350001_P01_FRONT-DECOR-BLOCK-ASSY-DL_CAD (Autodesk Fusion 360 design; units mm, degrees)
description: FRONT - DECOR BLOCK ASSY - DL | Khối trang trí trái (cụm) | P01
part number: 350001
description: FRONT - DECOR SKIN - DL | Tấm ốp alu khối trái | P01
part number: 351101
description: FRONT - DECOR BACK PLATE - DL | Tấm hậu khối trái | P01
part number: 351102
description: FRONT - DOOR HINGE-SIDE STOP - DL - PIECE 1 | Mặt trước - nẹp chặn cửa phía bản lề - khối trái - đoạn 1 | P01
part number: 351105
description: FRONT - DOOR HINGE-SIDE STOP - DL - PIECE 2 AND 3 | Mặt trước - nẹp chặn cửa phía bản lề - khối trái - đoạn 2 và 3 | P01
part number: 351106
description: FRONT - DOOR HINGE-SIDE STOP - DL - PIECE 4 | Mặt trước - nẹp chặn cửa phía bản lề - khối trái - đoạn 4 | P01
part number: 351107
description: FRONT - FRAME-STOP SEAL - HINGE SIDE 1 | Gioăng chặn cửa phía bản lề | P01
part number: 368005
description: FRONT - FRAME-STOP SEAL - HINGE SIDE 2 AND 3 | Gioăng chặn cửa phía bản lề | P01
description: FRONT - FRAME-STOP SEAL - HINGE SIDE 4 | Gioăng chặn cửa phía bản lề | P01
description: FRONT - DECOR FRAME - DL | Khung trang trí trái (hàn) | P01
part number: 351104
description: FRONT - DECOR FRAME DL - BACK RING BOTTOM | Mặt trước - khung khối trái - vòng sau - thanh dưới | P01
part number: 352101
description: FRONT - DECOR FRAME DL - BACK RING DOOR SIDE | Mặt trước - khung khối trái - vòng sau - thanh phía cửa | P01
part number: 352102
description: FRONT - DECOR FRAME DL - BACK RING SLOPE UNDER DT | Mặt trước - khung khối trái - vòng sau - thanh dốc dưới khối trên | P01
part number: 352103
description: FRONT - DECOR FRAME DL - BACK RING BOLT LINE | Mặt trước - khung khối trái - vòng sau - thanh hàng bu lông | P01
part number: 352104
description: FRONT - DECOR FRAME DL - RING DOOR SIDE - RINGS 1 TO 4 | Mặt trước - khung khối trái - vòng ngang - thanh phía cửa (vòng 1 đến 4) | P01
part number: 352105
description: FRONT - DECOR FRAME DL - RING BACK - RINGS 1 TO 4 | Mặt trước - khung khối trái - vòng ngang - thanh phía sau (vòng 1 đến 4) | P01
part number: 352106
description: FRONT - DECOR FRAME DL - RING BOTTOM - OUTER FACET | Mặt trước - khung khối trái - vòng dưới - thanh mặt vát ngoài | P01
part number: 352107
description: FRONT - DECOR FRAME DL - RING BOTTOM - FRONT FACET | Mặt trước - khung khối trái - vòng dưới - thanh mặt vát trước | P01
part number: 352108
description: FRONT - DECOR FRAME DL - RING OUTER FACET - RINGS 2 TO 4 | Mặt trước - khung khối trái - vòng ngang - thanh mặt vát ngoài (vòng 2 đến 4) | P01
part number: 352109
description: FRONT - DECOR FRAME DL - RING FRONT FACET - RINGS 2 TO 4 | Mặt trước - khung khối trái - vòng ngang - thanh mặt vát trước (vòng 2 đến 4) | P01
part number: 352110
description: FRONT - DECOR FRAME DL - HINGE POST 1 | Mặt trước - khung khối trái - trụ bản lề 1 | P01
part number: 352111
description: FRONT - DECOR FRAME DL - DOOR-SIDE FRONT POST 1 | Mặt trước - khung khối trái - trụ trước phía cửa 1 | P01
part number: 352112
description: FRONT - DECOR FRAME DL - HINGE POST 2 | Mặt trước - khung khối trái - trụ bản lề 2 | P01
part number: 352113
description: FRONT - DECOR FRAME DL - DOOR-SIDE FRONT POST 2 | Mặt trước - khung khối trái - trụ trước phía cửa 2 | P01
part number: 352114
description: FRONT - DECOR FRAME DL - HINGE POST 3 | Mặt trước - khung khối trái - trụ bản lề 3 | P01
part number: 352115
description: FRONT - DECOR FRAME DL - DOOR-SIDE FRONT POST 3 | Mặt trước - khung khối trái - trụ trước phía cửa 3 | P01
part number: 352116
Autodesk Fusion 360 part; units mm, degrees
(part 1 of 3)
sketch "PLAN - DL FACETS (SKELETON)" plane through (0, 0, 0) normal (0, 0, 1) x (1, 0, 0) in component "351101 FRONT - DECOR SKIN - DL"
  line L0 (-1250, -645) -> (-1250, -670)
  line L1 (-1250, -670) -> (-1158, -752)
  line L2 (-1158, -752) -> (-979, -844)
  line L3 (-979, -844) -> (-972, -844)
  line L4 (-972, -844) -> (-972, -645)
  line L5 (-972, -645) -> (-1250, -645)
  point P0 (-5000, -5000)
  dimension "d3208" = 5000
  dimension "d3209" = 5000
  dimension "d3210" = 3750
  dimension "d3211" = 3842
  dimension "d3212" = 4021
  dimension "d3213" = 4028
  dimension "d3214" = 4330
  dimension "d3215" = 4248
  dimension "d3216" = 4156
  dimension "d3217" = 4355
  constraint vertical L0
  constraint vertical L4
  constraint horizontal L3
  constraint horizontal L5
  measures "d3208" horizontal distance of origin P0
  measures "d3209" vertical distance of origin P0
  measures "d3210" horizontal distance of L0.start P0
  measures "d3211" horizontal distance of L1.end P0
  measures "d3212" horizontal distance of L2.end P0
  measures "d3213" horizontal distance of L3.end P0
  measures "d3214" vertical distance of L0.end P0
  measures "d3215" vertical distance of L1.end P0
  measures "d3216" vertical distance of L2.end P0
  measures "d3217" vertical distance of L4.end P0
extrude "EXTRUDE - DL OUTER SHAPE" add sketch "PLAN - DL FACETS (SKELETON)" along normal blind 2290 from surface at 110 makes body 1 in component "351101 FRONT - DECOR SKIN - DL"
sketch "SLOPE - DL TOP UNDER DT" plane through (0, 0, 0) normal (0, 1, 0) x (1, 0, 0) in component "351101 FRONT - DECOR SKIN - DL"
  line L0 (-1250, -2397) -> (-972, -2120)
  line L1 (-972, -2120) -> (-972, -2400)
  line L2 (-972, -2400) -> (-1250, -2400)
  line L3 (-1250, -2400) -> (-1250, -2397)
  point P0 (-5000, 5000)
  dimension "d3221" = 5000
  dimension "d3222" = 5000
  dimension "d3223" = 4028
  dimension "d3224" = 3750
  constraint vertical L1
  constraint vertical L3
  constraint horizontal L2
  measures "d3221" horizontal distance of origin P0
  measures "d3222" vertical distance of origin P0
  measures "d3223" horizontal distance of L0.end P0
  measures "d3224" horizontal distance of L2.end P0
extrude "CUT - DL TOP SLOPE" cut sketch "SLOPE - DL TOP UNDER DT" along normal blind 205 from surface at -850 bodies 1 in component "351101 FRONT - DECOR SKIN - DL"
shell "SHELL - DL SKIN 3 MM (OPEN AT THE BACK AND UNDER DT)" thickness 3 removed faces 3 at (-1036.3333, -747, 110) at (-1036.3333, -747, 2184.1019) at (-1157.3333, -645, 1542.3333) on bodies 1 in component "351101 FRONT - DECOR SKIN - DL"
sketch "POCKET - HINGE H1 (HOLD SPACE)" plane through (0, 0, 0) normal (0, 0, 1) x (1, 0, 0) in component "351101 FRONT - DECOR SKIN - DL"
  line L0 (-1134, -721) -> (-971, -721)
  line L1 (-971, -721) -> (-971, -677)
  line L2 (-971, -677) -> (-1134, -677)
  line L3 (-1134, -677) -> (-1134, -721)
  point P0 (-5000, -5000)
  dimension "d3232" = 5000
  dimension "d3233" = 5000
  dimension "d3234" = 4029
  dimension "d3235" = 3866
  dimension "d3236" = 4279
  dimension "d3237" = 4323
  constraint vertical L1
  constraint vertical L3
  constraint horizontal L0
  constraint horizontal L2
  measures "d3232" horizontal distance of origin P0
  measures "d3233" vertical distance of origin P0
  measures "d3234" horizontal distance of L0.end P0
  measures "d3235" horizontal distance of L2.end P0
  measures "d3236" vertical distance of L0.start P0
  measures "d3237" vertical distance of L1.end P0
extrude "CUT - HINGE POCKET H1 IN THE SKIN" cut sketch "POCKET - HINGE H1 (HOLD SPACE)" along normal blind 124 from surface at 293 bodies 1 in component "351101 FRONT - DECOR SKIN - DL"
sketch "POCKET - HINGE H2 (HOLD SPACE)" plane through (0, 0, 0) normal (0, 0, 1) x (1, 0, 0) in component "351101 FRONT - DECOR SKIN - DL"
  line L0 (-1134, -721) -> (-971, -721)
  line L1 (-971, -721) -> (-971, -677)
  line L2 (-971, -677) -> (-1134, -677)
  line L3 (-1134, -677) -> (-1134, -721)
  point P0 (-5000, -5000)
  dimension "d3241" = 5000
  dimension "d3242" = 5000
  dimension "d3243" = 4029
  dimension "d3244" = 3866
  dimension "d3245" = 4279
  dimension "d3246" = 4323
  constraint vertical L1
  constraint vertical L3
  constraint horizontal L0
  constraint horizontal L2
  measures "d3241" horizontal distance of origin P0
  measures "d3242" vertical distance of origin P0
  measures "d3243" horizontal distance of L0.end P0
  measures "d3244" horizontal distance of L2.end P0
  measures "d3245" vertical distance of L0.start P0
  measures "d3246" vertical distance of L1.end P0
extrude "CUT - HINGE POCKET H2 IN THE SKIN" cut sketch "POCKET - HINGE H2 (HOLD SPACE)" along normal blind 124 from surface at 1047.5 bodies 1 in component "351101 FRONT - DECOR SKIN - DL"
sketch "POCKET - HINGE H3 (HOLD SPACE)" plane through (0, 0, 0) normal (0, 0, 1) x (1, 0, 0) in component "351101 FRONT - DECOR SKIN - DL"
  line L0 (-1134, -721) -> (-971, -721)
  line L1 (-971, -721) -> (-971, -677)
  line L2 (-971, -677) -> (-1134, -677)
  line L3 (-1134, -677) -> (-1134, -721)
  point P0 (-5000, -5000)
  dimension "d3250" = 5000
  dimension "d3251" = 5000
  dimension "d3252" = 4029
  dimension "d3253" = 3866
  dimension "d3254" = 4279
  dimension "d3255" = 4323
  constraint vertical L1
  constraint vertical L3
  constraint horizontal L0
  constraint horizontal L2
  measures "d3250" horizontal distance of origin P0
  measures "d3251" vertical distance of origin P0
  measures "d3252" horizontal distance of L0.end P0
  measures "d3253" horizontal distance of L2.end P0
  measures "d3254" vertical distance of L0.start P0
  measures "d3255" vertical distance of L1.end P0
extrude "CUT - HINGE POCKET H3 IN THE SKIN" cut sketch "POCKET - HINGE H3 (HOLD SPACE)" along normal blind 124 from surface at 1802 bodies 1 in component "351101 FRONT - DECOR SKIN - DL"
sketch "OUTLINE - DL BACK PLATE" plane through (0, 0, 0) normal (0, 1, 0) x (1, 0, 0) in component "351102 FRONT - DECOR BACK PLATE - DL"
  line L0 (-1247, -113) -> (-975, -113)
  line L1 (-975, -113) -> (-975, -2122.9892)
  line L2 (-975, -2122.9892) -> (-1247, -2394.0108)
  line L3 (-1247, -2394.0108) -> (-1247, -113)
  point P0 (-5000, 5000)
  dimension "d3259" = 5000
  dimension "d3260" = 5000
  dimension "d3261" = 4025
  dimension "d3262" = 3753
  dimension "d3263" = 5113
  dimension "d3264" = 7122.9892
  dimension "d3265" = 7394.0108
  constraint vertical L1
  constraint vertical L3
  constraint horizontal L0
  measures "d3259" horizontal distance of origin P0
  measures "d3260" vertical distance of origin P0
  measures "d3261" horizontal distance of L0.end P0
  measures "d3262" horizontal distance of L2.end P0
  measures "d3263" vertical distance of L0.start P0
  measures "d3264" vertical distance of L1.end P0
  measures "d3265" vertical distance of L2.end P0
extrude "EXTRUDE - DL BACK PLATE" add sketch "OUTLINE - DL BACK PLATE" along normal blind 2 from surface at -647 separate body makes body 2 in component "351102 FRONT - DECOR BACK PLATE - DL"
sketch "HOLES - J-FRONT-01 RIVNUTS (6)" plane through (0, 0, 0) normal (0, 1, 0) x (1, 0, 0) in component "351102 FRONT - DECOR BACK PLATE - DL"
  circle A0 centre (-1224, -332.26) radius 4.765
  circle A1 centre (-1224, -683.63) radius 4.765
  circle A2 centre (-1224, -1035) radius 4.765
  circle A3 centre (-1224, -1477.26) radius 4.765
  circle A4 centre (-1224, -1828.63) radius 4.765
  circle A5 centre (-1224, -2180) radius 4.765
  point P0 (-5000, 5000)
  dimension "d3269" = 5000
  dimension "d3270" = 5000
  dimension "d3272" = 5332.26
  dimension "d3273" = 9.53
  dimension "d3275" = 5683.63
  dimension "d3276" = 9.53
  dimension "d3278" = 6035
  dimension "d3279" = 9.53
  dimension "d3281" = 6477.26
  dimension "d3282" = 9.53
  dimension "d3284" = 6828.63
  dimension "d3285" = 9.53
  dimension "d3287" = 7180
  dimension "d3288" = 9.53
  measures "d3269" horizontal distance of origin P0
  measures "d3270" vertical distance of origin P0
  measures "d3272" vertical distance of P0 A0.centre
  measures "d3273" diameter of A0
  measures "d3275" vertical distance of P0 A1.centre
  measures "d3276" diameter of A1
  measures "d3278" vertical distance of P0 A2.centre
  measures "d3279" diameter of A2
  measures "d3281" vertical distance of P0 A3.centre
  measures "d3282" diameter of A3
  measures "d3284" vertical distance of P0 A4.centre
  measures "d3285" diameter of A4
  measures "d3287" vertical distance of P0 A5.centre
  measures "d3288" diameter of A5
extrude "CUT - J-FRONT-01 RIVNUT HOLES" cut sketch "HOLES - J-FRONT-01 RIVNUTS (6)" along normal blind 4 from surface at -648 bodies 2 in component "351102 FRONT - DECOR BACK PLATE - DL"
sketch "TUBE ST1 - HINGE-SIDE STOP 1 (ANGLE, BONDED)" plane through (0, 0, 0) normal (0, 0, 1) x (1, 0, 0) in component "351105 FRONT - DOOR HINGE-SIDE STOP - DL - PIECE 1"
  line L0 (-972, -690.62) -> (-942, -690.62)
  line L1 (-942, -690.62) -> (-942, -688.62)
  line L2 (-942, -688.62) -> (-970, -688.62)
  line L3 (-970, -688.62) -> (-970, -670.62)
  line L4 (-970, -670.62) -> (-972, -670.62)
  line L5 (-972, -670.62) -> (-972, -690.62)
  point P0 (-5000, -5000)
  dimension "d3292" = 5000
  dimension "d3293" = 5000
  dimension "d3294" = 4058
  dimension "d3295" = 4030
  dimension "d3296" = 4028
  dimension "d3297" = 4309.38
  dimension "d3298" = 4311.38
  dimension "d3299" = 4329.38
  constraint vertical L1
  constraint vertical L3
  constraint vertical L5
  constraint horizontal L0
  constraint horizontal L2
  constraint horizontal L4
  measures "d3292" horizontal distance of origin P0
  measures "d3293" vertical distance of origin P0
  measures "d3294" horizontal distance of L0.end P0
  measures "d3295" horizontal distance of L2.end P0
  measures "d3296" horizontal distance of L4.end P0
  measures "d3297" vertical distance of L0.start P0
  measures "d3298" vertical distance of L1.end P0
  measures "d3299" vertical distance of L3.end P0
extrude "EXTRUDE - TUBE ST1" add sketch "TUBE ST1 - HINGE-SIDE STOP 1 (ANGLE, BONDED)" along normal blind 180 from surface at 105 separate body makes body 3 in component "351105 FRONT - DOOR HINGE-SIDE STOP - DL - PIECE 1"
sketch "TUBE ST2 - HINGE-SIDE STOP 2 (ANGLE, BONDED)" plane through (0, 0, 0) normal (0, 0, 1) x (1, 0, 0) in component "351106 FRONT - DOOR HINGE-SIDE STOP - DL - PIECE 2 AND 3"
  line L0 (-972, -690.62) -> (-942, -690.62)
  line L1 (-942, -690.62) -> (-942, -688.62)
  line L2 (-942, -688.62) -> (-970, -688.62)
  line L3 (-970, -688.62) -> (-970, -670.62)
  line L4 (-970, -670.62) -> (-972, -670.62)
  line L5 (-972, -670.62) -> (-972, -690.62)
  point P0 (-5000, -5000)
  dimension "d3303" = 5000
  dimension "d3304" = 5000
  dimension "d3305" = 4058
  dimension "d3306" = 4030
  dimension "d3307" = 4028
  dimension "d3308" = 4309.38
  dimension "d3309" = 4311.38
  dimension "d3310" = 4329.38
  constraint vertical L1
  constraint vertical L3
  constraint vertical L5
  constraint horizontal L0
  constraint horizontal L2
  constraint horizontal L4
  measures "d3303" horizontal distance of origin P0
  measures "d3304" vertical distance of origin P0
  measures "d3305" horizontal distance of L0.end P0
  measures "d3306" horizontal distance of L2.end P0
  measures "d3307" horizontal distance of L4.end P0
  measures "d3308" vertical distance of L0.start P0
  measures "d3309" vertical distance of L1.end P0
  measures "d3310" vertical distance of L3.end P0
extrude "EXTRUDE - TUBE ST2" add sketch "TUBE ST2 - HINGE-SIDE STOP 2 (ANGLE, BONDED)" along normal blind 614.5 from surface at 425 separate body makes body 4 in component "351106 FRONT - DOOR HINGE-SIDE STOP - DL - PIECE 2 AND 3"
ref_plane "WorkPlane3" through (0, 0, 754.5) normal (0, 0, 1) x (1, 0, 0)
sketch "TUBE ST4 - HINGE-SIDE STOP 4 (ANGLE, BONDED)" plane through (0, 0, 0) normal (0, 0, 1) x (1, 0, 0) in component "351107 FRONT - DOOR HINGE-SIDE STOP - DL - PIECE 4"
  line L0 (-972, -690.62) -> (-942, -690.62)
  line L1 (-942, -690.62) -> (-942, -688.62)
  line L2 (-942, -688.62) -> (-970, -688.62)
  line L3 (-970, -688.62) -> (-970, -670.62)
  line L4 (-970, -670.62) -> (-972, -670.62)
  line L5 (-972, -670.62) -> (-972, -690.62)
  point P0 (-5000, -5000)
  dimension "d3320" = 5000
  dimension "d3321" = 5000
  dimension "d3322" = 4058
  dimension "d3323" = 4030
  dimension "d3324" = 4028
  dimension "d3325" = 4309.38
  dimension "d3326" = 4311.38
  dimension "d3327" = 4329.38
  constraint vertical L1
  constraint vertical L3
  constraint vertical L5
  constraint horizontal L0
  constraint horizontal L2
  constraint horizontal L4
  measures "d3320" horizontal distance of origin P0
  measures "d3321" vertical distance of origin P0
  measures "d3322" horizontal distance of L0.end P0
  measures "d3323" horizontal distance of L2.end P0
  measures "d3324" horizontal distance of L4.end P0
  measures "d3325" vertical distance of L0.start P0
  measures "d3326" vertical distance of L1.end P0
  measures "d3327" vertical distance of L3.end P0
extrude "EXTRUDE - TUBE ST4" add sketch "TUBE ST4 - HINGE-SIDE STOP 4 (ANGLE, BONDED)" along normal blind 166 from surface at 1934 separate body makes body 5 in component "351107 FRONT - DOOR HINGE-SIDE STOP - DL - PIECE 4"
sketch "TUBE PS1 - FRAME-STOP SEAL PS 1515 - HINGE SIDE 1" plane through (0, 0, 0) normal (0, 0, 1) x (1, 0, 0) in component "368005 FRONT - FRAME-STOP SEAL - HINGE SIDE 1"
  line L0 (-961, -694.62) -> (-946, -694.62)
  line L1 (-946, -694.62) -> (-946, -690.62)
  line L2 (-946, -690.62) -> (-961, -690.62)
  line L3 (-961, -690.62) -> (-961, -694.62)
  point P0 (-5000, -5000)
  dimension "d3331" = 5000
  dimension "d3332" = 5000
  dimension "d3333" = 4054
  dimension "d3334" = 4039
  dimension "d3335" = 4305.38
  dimension "d3336" = 4309.38
  constraint vertical L1
  constraint vertical L3
  constraint horizontal L0
  constraint horizontal L2
  measures "d3331" horizontal distance of origin P0
  measures "d3332" vertical distance of origin P0
  measures "d3333" horizontal distance of L0.end P0
  measures "d3334" horizontal distance of L2.end P0
  measures "d3335" vertical distance of L0.start P0
  measures "d3336" vertical distance of L1.end P0
extrude "EXTRUDE - TUBE PS1" add sketch "TUBE PS1 - FRAME-STOP SEAL PS 1515 - HINGE SIDE 1" along normal blind 180 from surface at 105 separate body makes body 6 in component "368005 FRONT - FRAME-STOP SEAL - HINGE SIDE 1"
sketch "TUBE PS2 - FRAME-STOP SEAL PS 1515 - HINGE SIDE 2" plane through (0, 0, 0) normal (0, 0, 1) x (1, 0, 0) in component "368005 FRONT - FRAME-STOP SEAL - HINGE SIDE 2 AND 3"
  line L0 (-961, -694.62) -> (-946, -694.62)
  line L1 (-946, -694.62) -> (-946, -690.62)
  line L2 (-946, -690.62) -> (-961, -690.62)
  line L3 (-961, -690.62) -> (-961, -694.62)
  point P0 (-5000, -5000)
  dimension "d3340" = 5000
  dimension "d3341" = 5000
  dimension "d3342" = 4054
  dimension "d3343" = 4039
  dimension "d3344" = 4305.38
  dimension "d3345" = 4309.38
  constraint vertical L1
  constraint vertical L3
  constraint horizontal L0
  constraint horizontal L2
  measures "d3340" horizontal distance of origin P0
  measures "d3341" vertical distance of origin P0
  measures "d3342" horizontal distance of L0.end P0
  measures "d3343" horizontal distance of L2.end P0
  measures "d3344" vertical distance of L0.start P0
  measures "d3345" vertical distance of L1.end P0
extrude "EXTRUDE - TUBE PS2" add sketch "TUBE PS2 - FRAME-STOP SEAL PS 1515 - HINGE SIDE 2" along normal blind 614.5 from surface at 425 separate body makes body 7 in component "368005 FRONT - FRAME-STOP SEAL - HINGE SIDE 2 AND 3"
ref_plane "WorkPlane4" through (0, 0, 754.5) normal (0, 0, 1) x (1, 0, 0)
sketch "TUBE PS4 - FRAME-STOP SEAL PS 1515 - HINGE SIDE 4" plane through (0, 0, 0) normal (0, 0, 1) x (1, 0, 0) in component "368005 FRONT - FRAME-STOP SEAL - HINGE SIDE 4"
  line L0 (-961, -694.62) -> (-946, -694.62)
  line L1 (-946, -694.62) -> (-946, -690.62)
  line L2 (-946, -690.62) -> (-961, -690.62)
  line L3 (-961, -690.62) -> (-961, -694.62)
  point P0 (-5000, -5000)
  dimension "d3355" = 5000
  dimension "d3356" = 5000
  dimension "d3357" = 4054
  dimension "d3358" = 4039
  dimension "d3359" = 4305.38
  dimension "d3360" = 4309.38
  constraint vertical L1
  constraint vertical L3
  constraint horizontal L0
  constraint horizontal L2
  measures "d3355" horizontal distance of origin P0
  measures "d3356" vertical distance of origin P0
  measures "d3357" horizontal distance of L0.end P0
  measures "d3358" horizontal distance of L2.end P0
  measures "d3359" vertical distance of L0.start P0
  measures "d3360" vertical distance of L1.end P0
extrude "EXTRUDE - TUBE PS4" add sketch "TUBE PS4 - FRAME-STOP SEAL PS 1515 - HINGE SIDE 4" along normal blind 171 from surface at 1934 separate body makes body 8 in component "368005 FRONT - FRAME-STOP SEAL - HINGE SIDE 4"
sketch "TUBE B01 - BACK RING BOTTOM" plane through (0, 0, 0) normal (0, 1, 0) x (1, 0, 0) in component "352101 FRONT - DECOR FRAME DL - BACK RING BOTTOM"
  line L0 (-1244, -110) -> (-978, -110)
  line L1 (-978, -110) -> (-998, -130)
  line L2 (-998, -130) -> (-1184, -130)
  line L3 (-1184, -130) -> (-1244, -110)
  point P0 (-5000, 5000)
  dimension "d3364" = 5000
  dimension "d3365" = 5000
  dimension "d3366" = 3756
  dimension "d3367" = 4022
  dimension "d3368" = 4002
  dimension "d3369" = 3816
  dimension "d3370" = 5110
  dimension "d3371" = 5130
  constraint horizontal L0
  constraint horizontal L2
  measures "d3364" horizontal distance of origin P0
  measures "d3365" vertical distance of origin P0
  measures "d3366" horizontal distance of L0.start P0
  measures "d3367" horizontal distance of L0.end P0
  measures "d3368" horizontal distance of L1.end P0
  measures "d3369" horizontal distance of L2.end P0
  measures "d3370" vertical distance of L0.start P0
  measures "d3371" vertical distance of L1.end P0
extrude "EXTRUDE - TUBE B01" add sketch "TUBE B01 - BACK RING BOTTOM" along normal blind 20 from surface at -667 separate body makes body 9 in component "352101 FRONT - DECOR FRAME DL - BACK RING BOTTOM"
shell "SHELL - TUBE B01 (ENDS OPEN)" thickness 1.5 removed faces 2 at (-1204, -660.3333, 123.3333) at (-984.6667, -660.3333, 116.6667) on bodies 9 in component "352101 FRONT - DECOR FRAME DL - BACK RING BOTTOM"
sketch "TUBE B02 - BACK RING DOOR SIDE" plane through (0, 0, 0) normal (0, 1, 0) x (1, 0, 0) in component "352102 FRONT - DECOR FRAME DL - BACK RING DOOR SIDE"
  line L0 (-978, -110) -> (-978, -2121.7434)
  line L1 (-978, -2121.7434) -> (-998, -2113.438)
  line L2 (-998, -2113.438) -> (-998, -130)
  line L3 (-998, -130) -> (-978, -110)
  point P0 (-5000, 5000)
  dimension "d3376" = 5000
  dimension "d3377" = 5000
  dimension "d3378" = 4022
  dimension "d3379" = 4002
  dimension "d3380" = 5110
  dimension "d3381" = 7121.7434
  dimension "d3382" = 7113.438
  dimension "d3383" = 5130
  constraint vertical L0
  constraint vertical L2
  measures "d3376" horizontal distance of origin P0
  measures "d3377" vertical distance of origin P0
  measures "d3378" horizontal distance of L0.start P0
  measures "d3379" horizontal distance of L1.end P0
  measures "d3380" vertical distance of L0.start P0
  measures "d3381" vertical distance of L0.end P0
  measures "d3382" vertical distance of L1.end P0
  measures "d3383" vertical distance of L2.end P0
extrude "EXTRUDE - TUBE B02" add sketch "TUBE B02 - BACK RING DOOR SIDE" along normal blind 20 from surface at -667 separate body makes body 10 in component "352102 FRONT - DECOR FRAME DL - BACK RING DOOR SIDE"
shell "SHELL - TUBE B02 (ENDS OPEN)" thickness 1.5 removed faces 2 at (-991.3333, -660.3333, 123.3333) at (-984.6667, -660.3333, 2118.9749) on bodies 10 in component "352102 FRONT - DECOR FRAME DL - BACK RING DOOR SIDE"
sketch "TUBE B03 - BACK RING SLOPE UNDER DT" plane through (0, 0, 0) normal (0, 1, 0) x (1, 0, 0) in component "352103 FRONT - DECOR FRAME DL - BACK RING SLOPE UNDER DT"
  line L0 (-978, -2121.7434) -> (-1244, -2386.7866)
  line L1 (-1244, -2386.7866) -> (-1184, -2298.7689)
  line L2 (-1184, -2298.7689) -> (-998, -2113.438)
  line L3 (-998, -2113.438) -> (-978, -2121.7434)
  point P0 (-5000, 5000)
  dimension "d3388" = 5000
  dimension "d3389" = 5000
  dimension "d3390" = 4022
  dimension "d3391" = 3756
  dimension "d3392" = 3816
  dimension "d3393" = 4002
  dimension "d3394" = 7121.7434
  dimension "d3395" = 7386.7866
  dimension "d3396" = 7298.7689
  dimension "d3397" = 7113.438
  measures "d3388" horizontal distance of origin P0
  measures "d3389" vertical distance of origin P0
  measures "d3390" horizontal distance of L0.start P0
  measures "d3391" horizontal distance of L0.end P0
  measures "d3392" horizontal distance of L1.end P0
  measures "d3393" horizontal distance of L2.end P0
  measures "d3394" vertical distance of L0.start P0
  measures "d3395" vertical distance of L0.end P0
  measures "d3396" vertical distance of L1.end P0
  measures "d3397" vertical distance of L2.end P0
extrude "EXTRUDE - TUBE B03" add sketch "TUBE B03 - BACK RING SLOPE UNDER DT" along normal blind 20 from surface at -667 separate body makes body 11 in component "352103 FRONT - DECOR FRAME DL - BACK RING SLOPE UNDER DT"
shell "SHELL - TUBE B03 (ENDS OPEN)" thickness 1.5 removed faces 2 at (-991.3333, -660.3333, 2116.2065) at (-1224, -660.3333, 2357.4474) on bodies 11 in component "352103 FRONT - DECOR FRAME DL - BACK RING SLOPE UNDER DT"
sketch "TUBE B04 - BACK RING BOLT LINE" plane through (0, 0, 0) normal (0, 1, 0) x (1, 0, 0) in component "352104 FRONT - DECOR FRAME DL - BACK RING BOLT LINE"
  line L0 (-1244, -2386.7866) -> (-1244, -110)
  line L1 (-1244, -110) -> (-1184, -130)
  line L2 (-1184, -130) -> (-1184, -2298.7689)
  line L3 (-1184, -2298.7689) -> (-1244, -2386.7866)
  point P0 (-5000, 5000)
  dimension "d3402" = 5000
  dimension "d3403" = 5000
  dimension "d3404" = 3756
  dimension "d3405" = 3816
  dimension "d3406" = 7386.7866
  dimension "d3407" = 5110
  dimension "d3408" = 5130
  dimension "d3409" = 7298.7689
  constraint vertical L0
  constraint vertical L2
  measures "d3402" horizontal distance of origin P0
  measures "d3403" vertical distance of origin P0
  measures "d3404" horizontal distance of L0.start P0
  measures "d3405" horizontal distance of L1.end P0
  measures "d3406" vertical distance of L0.start P0
  measures "d3407" vertical distance of L0.end P0
  measures "d3408" vertical distance of L1.end P0
  measures "d3409" vertical distance of L2.end P0
extrude "EXTRUDE - TUBE B04" add sketch "TUBE B04 - BACK RING BOLT LINE" along normal blind 20 from surface at -667 separate body makes body 12 in component "352104 FRONT - DECOR FRAME DL - BACK RING BOLT LINE"
shell "SHELL - TUBE B04 (ENDS OPEN)" thickness 1.5 removed faces 2 at (-1204, -660.3333, 2328.1082) at (-1224, -660.3333, 116.6667) on bodies 12 in component "352104 FRONT - DECOR FRAME DL - BACK RING BOLT LINE"
sketch "TUBE R1D - RING BOTTOM - DOOR SIDE" plane through (0, 0, 0) normal (0, 0, 1) x (1, 0, 0) in component "352105 FRONT - DECOR FRAME DL - RING DOOR SIDE - RINGS 1 TO 4"
  line L0 (-978, -837.7679) -> (-978, -670)
  line L1 (-978, -670) -> (-998, -690)
  line L2 (-998, -690) -> (-998, -827.4885)
  line L3 (-998, -827.4885) -> (-978, -837.7679)
  point P0 (-5000, -5000)
  dimension "d3414" = 5000
  dimension "d3415" = 5000
  dimension "d3416" = 4022
  dimension "d3417" = 4002
  dimension "d3418" = 4162.2321
  dimension "d3419" = 4330
  dimension "d3420" = 4310
  dimension "d3421" = 4172.5115
  constraint vertical L0
  constraint vertical L2
  measures "d3414" horizontal distance of origin P0
  measures "d3415" vertical distance of origin P0
  measures "d3416" horizontal distance of L0.start P0
  measures "d3417" horizontal distance of L1.end P0
  measures "d3418" vertical distance of L0.start P0
  measures "d3419" vertical distance of L0.end P0
  measures "d3420" vertical distance of L1.end P0
  measures "d3421" vertical distance of L2.end P0
extrude "EXTRUDE - TUBE R1D" add sketch "TUBE R1D - RING BOTTOM - DOOR SIDE" along normal blind 20 from surface at 110 separate body makes body 13 in component "352105 FRONT - DECOR FRAME DL - RING DOOR SIDE - RINGS 1 TO 4"
shell "SHELL - TUBE R1D (ENDS OPEN)" thickness 1.5 removed faces 2 at (-984.6667, -676.6667, 123.3333) at (-991.3333, -830.915, 116.6667) on bodies 13 in component "352105 FRONT - DECOR FRAME DL - RING DOOR SIDE - RINGS 1 TO 4"
sketch "TUBE R1K - RING BOTTOM - BACK" plane through (0, 0, 0) normal (0, 0, 1) x (1, 0, 0) in component "352106 FRONT - DECOR FRAME DL - RING BACK - RINGS 1 TO 4"
  line L0 (-978, -670) -> (-1240.9825, -670)
  line L1 (-1240.9825, -670) -> (-1188.485, -690)
  line L2 (-1188.485, -690) -> (-998, -690)
  line L3 (-998, -690) -> (-978, -670)
  point P0 (-5000, -5000)
  dimension "d3426" = 5000
  dimension "d3427" = 5000
  dimension "d3428" = 4022
  dimension "d3429" = 3759.0175
  dimension "d3430" = 3811.515
  dimension "d3431" = 4002
  dimension "d3432" = 4330
  dimension "d3433" = 4310
  constraint horizontal L0
  constraint horizontal L2
  measures "d3426" horizontal distance of origin P0
  measures "d3427" vertical distance of origin P0
  measures "d3428" horizontal distance of L0.start P0
  measures "d3429" horizontal distance of L0.end P0
  measures "d3430" horizontal distance of L1.end P0
  measures "d3431" horizontal distance of L2.end P0
  measures "d3432" vertical distance of L0.start P0
  measures "d3433" vertical distance of L1.end P0
extrude "EXTRUDE - TUBE R1K" add sketch "TUBE R1K - RING BOTTOM - BACK" along normal blind 20 from surface at 110 separate body makes body 14 in component "352106 FRONT - DECOR FRAME DL - RING BACK - RINGS 1 TO 4"
shell "SHELL - TUBE R1K (ENDS OPEN)" thickness 1.5 removed faces 2 at (-1223.4833, -676.6667, 116.6667) at (-991.3333, -683.3333, 116.6667) on bodies 14 in component "352106 FRONT - DECOR FRAME DL - RING BACK - RINGS 1 TO 4"
sketch "TUBE R1O - RING BOTTOM - OUTER FACET" plane through (0, 0, 0) normal (0, 0, 1) x (1, 0, 0) in component "352107 FRONT - DECOR FRAME DL - RING BOTTOM - OUTER FACET"
  line L0 (-1240.9825, -670) -> (-1154.5779, -747.0127)
  line L1 (-1154.5779, -747.0127) -> (-1143.1711, -730.3885)
  line L2 (-1143.1711, -730.3885) -> (-1188.485, -690)
  line L3 (-1188.485, -690) -> (-1240.9825, -670)
  point P0 (-5000, -5000)
  dimension "d3438" = 5000
  dimension "d3439" = 5000
  dimension "d3440" = 3759.0175
  dimension "d3441" = 3845.4221
  dimension "d3442" = 3856.8289
  dimension "d3443" = 3811.515
  dimension "d3444" = 4330
  dimension "d3445" = 4252.9873
  dimension "d3446" = 4269.6115
  dimension "d3447" = 4310
  measures "d3438" horizontal distance of origin P0
  measures "d3439" vertical distance of origin P0
  measures "d3440" horizontal distance of L0.start P0
  measures "d3441" horizontal distance of L0.end P0
  measures "d3442" horizontal distance of L1.end P0
  measures "d3443" horizontal distance of L2.end P0
  measures "d3444" vertical distance of L0.start P0
  measures "d3445" vertical distance of L0.end P0
  measures "d3446" vertical distance of L1.end P0
  measures "d3447" vertical distance of L2.end P0
extrude "EXTRUDE - TUBE R1O" add sketch "TUBE R1O - RING BOTTOM - OUTER FACET" along normal blind 20 from surface at 110 separate body makes body 15 in component "352107 FRONT - DECOR FRAME DL - RING BOTTOM - OUTER FACET"
shell "SHELL - TUBE R1O (ENDS OPEN)" thickness 1.5 removed faces 2 at (-1150.7757, -741.4713, 116.6667) at (-1205.9842, -683.3333, 116.6667) on bodies 15 in component "352107 FRONT - DECOR FRAME DL - RING BOTTOM - OUTER FACET"
sketch "TUBE R1F - RING BOTTOM - FRONT FACET" plane through (0, 0, 0) normal (0, 0, 1) x (1, 0, 0) in component "352108 FRONT - DECOR FRAME DL - RING BOTTOM - FRONT FACET"
  line L0 (-1154.5779, -747.0127) -> (-998, -827.4885)
  line L1 (-998, -827.4885) -> (-998, -805.0016)
  line L2 (-998, -805.0016) -> (-1143.1711, -730.3885)
  line L3 (-1143.1711, -730.3885) -> (-1154.5779, -747.0127)
  point P0 (-5000, -5000)
  dimension "d3452" = 5000
  dimension "d3453" = 5000
  dimension "d3454" = 3845.4221
  dimension "d3455" = 4002
  dimension "d3456" = 3856.8289
  dimension "d3457" = 4252.9873
  dimension "d3458" = 4172.5115
  dimension "d3459" = 4194.9984
  dimension "d3460" = 4269.6115
  constraint vertical L1
  measures "d3452" horizontal distance of origin P0
  measures "d3453" vertical distance of origin P0
  measures "d3454" horizontal distance of L0.start P0
  measures "d3455" horizontal distance of L0.end P0
  measures "d3456" horizontal distance of L2.end P0
  measures "d3457" vertical distance of L0.start P0
  measures "d3458" vertical distance of L0.end P0
  measures "d3459" vertical distance of L1.end P0
  measures "d3460" vertical distance of L2.end P0
extrude "EXTRUDE - TUBE R1F" add sketch "TUBE R1F - RING BOTTOM - FRONT FACET" along normal blind 20 from surface at 110 separate body makes body 16 in component "352108 FRONT - DECOR FRAME DL - RING BOTTOM - FRONT FACET"
shell "SHELL - TUBE R1F (ENDS OPEN)" thickness 1.5 removed faces 2 at (-998, -819.9929, 116.6667) at (-1146.9734, -735.9299, 116.6667) on bodies 16 in component "352108 FRONT - DECOR FRAME DL - RING BOTTOM - FRONT FACET"
ref_plane "WorkPlane1" through (0, 0, 612.25) normal (0, 0, 1) x (1, 0, 0) in component "351104 FRONT - DECOR FRAME - DL"
ref_plane "WorkPlane2" through (0, 0, 612.25) normal (0, 0, 1) x (1, 0, 0) in component "351104 FRONT - DECOR FRAME - DL"
sketch "TUBE R2O - RING BETWEEN HINGES 1 AND 2 - OUTER FACET" plane through (0, 0, 0) normal (0, 0, 1) x (1, 0, 0) in component "352109 FRONT - DECOR FRAME DL - RING OUTER FACET - RINGS 2 TO 4"
  line L0 (-1240.9825, -670) -> (-1154.5779, -747.0127)
  line L1 (-1154.5779, -747.0127) -> (-1143.1711, -730.3885)
  line L2 (-1143.1711, -730.3885) -> (-1188.485, -690)
  line L3 (-1188.485, -690) -> (-1240.9825, -670)
  point P0 (-5000, -5000)
  dimension "d3477" = 5000
  dimension "d3478" = 5000
  dimension "d3479" = 3759.0175
  dimension "d3480" = 3845.4221
  dimension "d3481" = 3856.8289
  dimension "d3482" = 3811.515
  dimension "d3483" = 4330
  dimension "d3484" = 4252.9873
  dimension "d3485" = 4269.6115
  dimension "d3486" = 4310
  measures "d3477" horizontal distance of origin P0
  measures "d3478" vertical distance of origin P0
  measures "d3479" horizontal distance of L0.start P0
  measures "d3480" horizontal distance of L0.end P0
  measures "d3481" horizontal distance of L1.end P0
  measures "d3482" horizontal distance of L2.end P0
  measures "d3483" vertical distance of L0.start P0
  measures "d3484" vertical distance of L0.end P0
  measures "d3485" vertical distance of L1.end P0
  measures "d3486" vertical distance of L2.end P0
extrude "EXTRUDE - TUBE R2O" add sketch "TUBE R2O - RING BETWEEN HINGES 1 AND 2 - OUTER FACET" along normal blind 20 from surface at 722.25 separate body makes body 17 in component "352109 FRONT - DECOR FRAME DL - RING OUTER FACET - RINGS 2 TO 4"
shell "SHELL - TUBE R2O (ENDS OPEN)" thickness 1.5 removed faces 2 at (-1150.7757, -741.4713, 728.9167) at (-1205.9842, -683.3333, 728.9167) on bodies 17 in component "352109 FRONT - DECOR FRAME DL - RING OUTER FACET - RINGS 2 TO 4"
sketch "TUBE R2F - RING BETWEEN HINGES 1 AND 2 - FRONT FACET" plane through (0, 0, 0) normal (0, 0, 1) x (1, 0, 0) in component "352110 FRONT - DECOR FRAME DL - RING FRONT FACET - RINGS 2 TO 4"
  line L0 (-1154.5779, -747.0127) -> (-998, -827.4885)
  line L1 (-998, -827.4885) -> (-998, -805.0016)
  line L2 (-998, -805.0016) -> (-1143.1711, -730.3885)
  line L3 (-1143.1711, -730.3885) -> (-1154.5779, -747.0127)
  point P0 (-5000, -5000)
  dimension "d3491" = 5000
  dimension "d3492" = 5000
  dimension "d3493" = 3845.4221
  dimension "d3494" = 4002
  dimension "d3495" = 3856.8289
  dimension "d3496" = 4252.9873
  dimension "d3497" = 4172.5115
  dimension "d3498" = 4194.9984
  dimension "d3499" = 4269.6115
  constraint vertical L1
  measures "d3491" horizontal distance of origin P0
  measures "d3492" vertical distance of origin P0
  measures "d3493" horizontal distance of L0.start P0
  measures "d3494" horizontal distance of L0.end P0
  measures "d3495" horizontal distance of L2.end P0
  measures "d3496" vertical distance of L0.start P0
  measures "d3497" vertical distance of L0.end P0
  measures "d3498" vertical distance of L1.end P0
  measures "d3499" vertical distance of L2.end P0
extrude "EXTRUDE - TUBE R2F" add sketch "TUBE R2F - RING BETWEEN HINGES 1 AND 2 - FRONT FACET" along normal blind 20 from surface at 722.25 separate body makes body 18 in component "352110 FRONT - DECOR FRAME DL - RING FRONT FACET - RINGS 2 TO 4"
shell "SHELL - TUBE R2F (ENDS OPEN)" thickness 1.5 removed faces 2 at (-998, -819.9929, 728.9167) at (-1146.9734, -735.9299, 728.9167) on bodies 18 in component "352110 FRONT - DECOR FRAME DL - RING FRONT FACET - RINGS 2 TO 4"
ref_plane "WorkPlane3" through (0, 0, 1366.75) normal (0, 0, 1) x (1, 0, 0) in component "351104 FRONT - DECOR FRAME - DL"
ref_plane "WorkPlane4" through (0, 0, 1366.75) normal (0, 0, 1) x (1, 0, 0) in component "351104 FRONT - DECOR FRAME - DL"
ref_plane "WorkPlane5" through (0, 0, 754.5) normal (0, 0, 1) x (1, 0, 0) in component "351104 FRONT - DECOR FRAME - DL"
ref_plane "WorkPlane6" through (0, 0, 754.5) normal (0, 0, 1) x (1, 0, 0) in component "351104 FRONT - DECOR FRAME - DL"
ref_plane "WorkPlane7" through (0, 0, 1991.7434) normal (0, 0, 1) x (1, 0, 0) in component "351104 FRONT - DECOR FRAME - DL"
ref_plane "WorkPlane8" through (0, 0, 1991.7434) normal (0, 0, 1) x (1, 0, 0) in component "351104 FRONT - DECOR FRAME - DL"
ref_plane "WorkPlane9" through (0, 0, 1379.4934) normal (0, 0, 1) x (1, 0, 0) in component "351104 FRONT - DECOR FRAME - DL"
ref_plane "WorkPlane10" through (0, 0, 1379.4934) normal (0, 0, 1) x (1, 0, 0) in component "351104 FRONT - DECOR FRAME - DL"
sketch "TUBE H1 - HINGE POST 1 (HINGE H1)" plane through (0, 0, 0) normal (0, 0, 1) x (1, 0, 0) in component "352111 FRONT - DECOR FRAME DL - HINGE POST 1"
  line L0 (-1154, -729) -> (-1134, -729)
  line L1 (-1134, -729) -> (-1134, -669)
  line L2 (-1134, -669) -> (-1154, -669)
  line L3 (-1154, -669) -> (-1154, -729)
  point P0 (-5000, -5000)
  dimension "d3552" = 5000
  dimension "d3553" = 5000
  dimension "d3554" = 3866
  dimension "d3555" = 3846
  dimension "d3556" = 4271
  dimension "d3557" = 4331
  constraint vertical L1
  constraint vertical L3
  constraint horizontal L0
  constraint horizontal L2
  measures "d3552" horizontal distance of origin P0
  measures "d3553" vertical distance of origin P0
  measures "d3554" horizontal distance of L0.end P0
  measures "d3555" horizontal distance of L2.end P0
  measures "d3556" vertical distance of L0.start P0
  measures "d3557" vertical distance of L1.end P0
extrude "EXTRUDE - TUBE H1" add sketch "TUBE H1 - HINGE POST 1 (HINGE H1)" along normal blind 592.25 from surface at 130 separate body makes body 19 in component "352111 FRONT - DECOR FRAME DL - HINGE POST 1"
shell "SHELL - TUBE H1 (ENDS OPEN)" thickness 1.5 removed faces 2 at (-1147.3333, -689, 722.25) at (-1147.3333, -689, 130) on bodies 19 in component "352111 FRONT - DECOR FRAME DL - HINGE POST 1"
sketch "TUBE P1 - DOOR-SIDE FRONT POST 1" plane through (0, 0, 0) normal (0, 0, 1) x (1, 0, 0) in component "352112 FRONT - DECOR FRAME DL - DOOR-SIDE FRONT POST 1"
  line L0 (-978, -827.4885) -> (-998, -827.4885)
  line L1 (-998, -827.4885) -> (-998, -807.4885)
  line L2 (-998, -807.4885) -> (-978, -807.4885)
  line L3 (-978, -807.4885) -> (-978, -827.4885)
  point P0 (-5000, -5000)
  dimension "d3562" = 5000
  dimension "d3563" = 5000
  dimension "d3564" = 4002
  dimension "d3565" = 4022
  dimension "d3566" = 4172.5115
  dimension "d3567" = 4192.5115
  constraint vertical L1
  constraint vertical L3
  constraint horizontal L0
  constraint horizontal L2
  measures "d3562" horizontal distance of origin P0
  measures "d3563" vertical distance of origin P0
  measures "d3564" horizontal distance of L0.end P0
  measures "d3565" horizontal distance of L2.end P0
  measures "d3566" vertical distance of L0.start P0
  measures "d3567" vertical distance of L1.end P0
extrude "EXTRUDE - TUBE P1" add sketch "TUBE P1 - DOOR-SIDE FRONT POST 1" along normal blind 592.25 from surface at 130 separate body makes body 20 in component "352112 FRONT - DECOR FRAME DL - DOOR-SIDE FRONT POST 1"
shell "SHELL - TUBE P1 (ENDS OPEN)" thickness 1.5 removed faces 2 at (-984.6667, -820.8219, 722.25) at (-984.6667, -820.8219, 130) on bodies 20 in component "352112 FRONT - DECOR FRAME DL - DOOR-SIDE FRONT POST 1"
sketch "TUBE H2 - HINGE POST 2 (HINGE H2)" plane through (0, 0, 0) normal (0, 0, 1) x (1, 0, 0) in component "352113 FRONT - DECOR FRAME DL - HINGE POST 2"
  line L0 (-1154, -729) -> (-1134, -729)
  line L1 (-1134, -729) -> (-1134, -669)
  line L2 (-1134, -669) -> (-1154, -669)
  line L3 (-1154, -669) -> (-1154, -729)
  point P0 (-5000, -5000)
  dimension "d3572" = 5000
  dimension "d3573" = 5000
  dimension "d3574" = 3866
  dimension "d3575" = 3846
  dimension "d3576" = 4271
  dimension "d3577" = 4331
  constraint vertical L1
  constraint vertical L3
  constraint horizontal L0
  constraint horizontal L2
  measures "d3572" horizontal distance of origin P0
  measures "d3573" vertical distance of origin P0
  measures "d3574" horizontal distance of L0.end P0
  measures "d3575" horizontal distance of L2.end P0
  measures "d3576" vertical distance of L0.start P0
  measures "d3577" vertical distance of L1.end P0
extrude "EXTRUDE - TUBE H2" add sketch "TUBE H2 - HINGE POST 2 (HINGE H2)" along normal blind 734.5 from surface at 742.25 separate body makes body 21 in component "352113 FRONT - DECOR FRAME DL - HINGE POST 2"
shell "SHELL - TUBE H2 (ENDS OPEN)" thickness 1.5 removed faces 2 at (-1147.3333, -689, 1476.75) at (-1147.3333, -689, 742.25) on bodies 21 in component "352113 FRONT - DECOR FRAME DL - HINGE POST 2"
sketch "TUBE P2 - DOOR-SIDE FRONT POST 2" plane through (0, 0, 0) normal (0, 0, 1) x (1, 0, 0) in component "352114 FRONT - DECOR FRAME DL - DOOR-SIDE FRONT POST 2"
  line L0 (-978, -827.4885) -> (-998, -827.4885)
  line L1 (-998, -827.4885) -> (-998, -807.4885)
  line L2 (-998, -807.4885) -> (-978, -807.4885)
  line L3 (-978, -807.4885) -> (-978, -827.4885)
  point P0 (-5000, -5000)
  dimension "d3582" = 5000
  dimension "d3583" = 5000
  dimension "d3584" = 4002
  dimension "d3585" = 4022
  dimension "d3586" = 4172.5115
  dimension "d3587" = 4192.5115
  constraint vertical L1
  constraint vertical L3
  constraint horizontal L0
  constraint horizontal L2
  measures "d3582" horizontal distance of origin P0
  measures "d3583" vertical distance of origin P0
  measures "d3584" horizontal distance of L0.end P0
  measures "d3585" horizontal distance of L2.end P0
  measures "d3586" vertical distance of L0.start P0
  measures "d3587" vertical distance of L1.end P0
extrude "EXTRUDE - TUBE P2" add sketch "TUBE P2 - DOOR-SIDE FRONT POST 2" along normal blind 734.5 from surface at 742.25 separate body makes body 22 in component "352114 FRONT - DECOR FRAME DL - DOOR-SIDE FRONT POST 2"
shell "SHELL - TUBE P2 (ENDS OPEN)" thickness 1.5 removed faces 2 at (-984.6667, -820.8219, 1476.75) at (-984.6667, -820.8219, 742.25) on bodies 22 in component "352114 FRONT - DECOR FRAME DL - DOOR-SIDE FRONT POST 2"
sketch "TUBE H3 - HINGE POST 3 (HINGE H3)" plane through (0, 0, 0) normal (0, 0, 1) x (1, 0, 0) in component "352115 FRONT - DECOR FRAME DL - HINGE POST 3"
  line L0 (-1154, -729) -> (-1134, -729)
  line L1 (-1134, -729) -> (-1134, -669)
  line L2 (-1134, -669) -> (-1154, -669)
  line L3 (-1154, -669) -> (-1154, -729)
  point P0 (-5000, -5000)
  dimension "d3592" = 5000
  dimension "d3593" = 5000
  dimension "d3594" = 3866
  dimension "d3595" = 3846
  dimension "d3596" = 4271
  dimension "d3597" = 4331
  constraint vertical L1
  constraint vertical L3
  constraint horizontal L0
  constraint horizontal L2
  measures "d3592" horizontal distance of origin P0
  measures "d3593" vertical distance of origin P0
  measures "d3594" horizontal distance of L0.end P0
  measures "d3595" horizontal distance of L2.end P0
  measures "d3596" vertical distance of L0.start P0
  measures "d3597" vertical distance of L1.end P0
extrude "EXTRUDE - TUBE H3" add sketch "TUBE H3 - HINGE POST 3 (HINGE H3)" along normal blind 604.9934 from surface at 1496.75 separate body makes body 23 in component "352115 FRONT - DECOR FRAME DL - HINGE POST 3"
shell "SHELL - TUBE H3 (ENDS OPEN)" thickness 1.5 removed faces 2 at (-1147.3333, -689, 2101.7434) at (-1147.3333, -689, 1496.75) on bodies 23 in component "352115 FRONT - DECOR FRAME DL - HINGE POST 3"
sketch "TUBE P3 - DOOR-SIDE FRONT POST 3" plane through (0, 0, 0) normal (0, 0, 1) x (1, 0, 0) in component "352116 FRONT - DECOR FRAME DL - DOOR-SIDE FRONT POST 3"
  line L0 (-978, -827.4885) -> (-998, -827.4885)
  line L1 (-998, -827.4885) -> (-998, -807.4885)
  line L2 (-998, -807.4885) -> (-978, -807.4885)
  line L3 (-978, -807.4885) -> (-978, -827.4885)
  point P0 (-5000, -5000)
  dimension "d3602" = 5000
  dimension "d3603" = 5000
  dimension "d3604" = 4002
  dimension "d3605" = 4022
  dimension "d3606" = 4172.5115
  dimension "d3607" = 4192.5115
  constraint vertical L1
  constraint vertical L3
  constraint horizontal L0
  constraint horizontal L2
  measures "d3602" horizontal distance of origin P0
  measures "d3603" vertical distance of origin P0
  measures "d3604" horizontal distance of L0.end P0
  measures "d3605" horizontal distance of L2.end P0
  measures "d3606" vertical distance of L0.start P0
  measures "d3607" vertical distance of L1.end P0
extrude "EXTRUDE - TUBE P3" add sketch "TUBE P3 - DOOR-SIDE FRONT POST 3" along normal blind 604.9934 from surface at 1496.75 separate body makes body 24 in component "352116 FRONT - DECOR FRAME DL - DOOR-SIDE FRONT POST 3"
shell "SHELL - TUBE P3 (ENDS OPEN)" thickness 1.5 removed faces 2 at (-984.6667, -820.8219, 2101.7434) at (-984.6667, -820.8219, 1496.75) on bodies 24 in component "352116 FRONT - DECOR FRAME DL - DOOR-SIDE FRONT POST 3"
sketch "HOLES - J-FRONT-01 RIVNUT TAILS AND BOLT TIPS (6)" plane through (0, 0, 0) normal (0, 1, 0) x (1, 0, 0) in component "352104 FRONT - DECOR FRAME DL - BACK RING BOLT LINE"
  circle A0 centre (-1224, -332.26) radius 7
  circle A1 centre (-1224, -683.63) radius 7
  circle A2 centre (-1224, -1035) radius 7
  circle A3 centre (-1224, -1477.26) radius 7
  circle A4 centre (-1224, -1828.63) radius 7
  circle A5 centre (-1224, -2180) radius 7
  point P0 (-5000, 5000)
  dimension "d3612" = 5000
  dimension "d3613" = 5000
  dimension "d3615" = 5332.26
  dimension "d3616" = 14
  dimension "d3618" = 5683.63
  dimension "d3619" = 14
  dimension "d3621" = 6035
  dimension "d3622" = 14
  dimension "d3624" = 6477.26
  dimension "d3625" = 14
  dimension "d3627" = 6828.63
  dimension "d3628" = 14
  dimension "d3630" = 7180
  dimension "d3631" = 14
  measures "d3612" horizontal distance of origin P0
  measures "d3613" vertical distance of origin P0
  measures "d3615" vertical distance of P0 A0.centre
  measures "d3616" diameter of A0
  measures "d3618" vertical distance of P0 A1.centre
  measures "d3619" diameter of A1
  measures "d3621" vertical distance of P0 A2.centre
  measures "d3622" diameter of A2
  measures "d3624" vertical distance of P0 A3.centre
  measures "d3625" diameter of A3
  measures "d3627" vertical distance of P0 A4.centre
  measures "d3628" diameter of A4
  measures "d3630" vertical distance of P0 A5.centre
  measures "d3631" diameter of A5
extrude "CUT - J-FRONT-01 RIVNUT TAILS AND BOLT TIPS" cut sketch "HOLES - J-FRONT-01 RIVNUT TAILS AND BOLT TIPS (6)" along normal blind 3 from surface at -649.5 bodies 12 in component "352104 FRONT - DECOR FRAME DL - BACK RING BOLT LINE"
sketch "HOLE - J-FRONT-02 SPIGOT (ROUND)" plane through (0, 0, 0) normal (0, 0, 1) x (1, 0, 0) in component "352107 FRONT - DECOR FRAME DL - RING BOTTOM - OUTER FACET"
  circle A0 centre (-1172.6574, -717.5028) radius 4.25
  point P0 (-5000, -5000)
  dimension "d3635" = 5000
  dimension "d3636" = 5000
  dimension "d3639" = 8.5
  measures "d3635" horizontal distance of origin P0
  measures "d3636" vertical distance of origin P0
  measures "d3639" diameter of A0
extrude "CUT - J-FRONT-02 SPIGOT HOLE" cut sketch "HOLE - J-FRONT-02 SPIGOT (ROUND)" along normal blind 3 from surface at 109 bodies 15 in component "352107 FRONT - DECOR FRAME DL - RING BOTTOM - OUTER FACET"
sketch "HOLES - J-FRONT-02 SPIGOT SLOT ENDS" plane through (0, 0, 0) normal (0, 0, 1) x (1, 0, 0) in component "352108 FRONT - DECOR FRAME DL - RING BOTTOM - FRONT FACET"
  circle A0 centre (-1079.3862, -774.4153) radius 4.25
  circle A1 centre (-1074.4945, -776.9295) radius 4.25
  point P0 (-5000, -5000)
  dimension "d3643" = 5000
  dimension "d3644" = 5000
  dimension "d3645" = 3920.6138
  dimension "d3646" = 4225.5847
  dimension "d3647" = 8.5
  dimension "d3648" = 3925.5055
  dimension "d3649" = 4223.0705
  dimension "d3650" = 8.5
  measures "d3643" horizontal distance of origin P0
  measures "d3644" vertical distance of origin P0
  measures "d3645" horizontal distance of P0 A0.centre
  measures "d3646" vertical distance of P0 A0.centre
  measures "d3647" diameter of A0
  measures "d3648" horizontal distance of P0 A1.centre
  measures "d3649" vertical distance of P0 A1.centre
  measures "d3650" diameter of A1
extrude "CUT - J-FRONT-02 SLOT ENDS" cut sketch "HOLES - J-FRONT-02 SPIGOT SLOT ENDS" along normal blind 3 from surface at 109 bodies 16 in component "352108 FRONT - DECOR FRAME DL - RING BOTTOM - FRONT FACET"